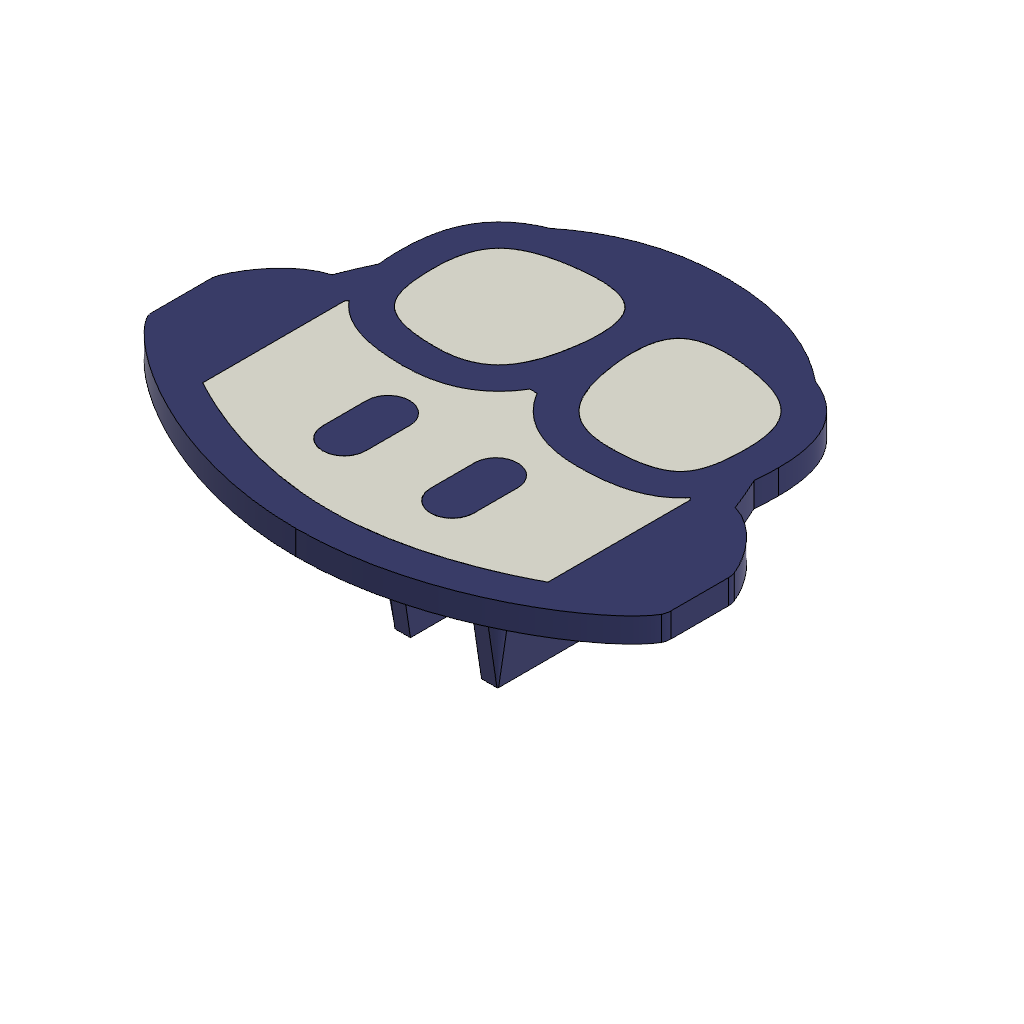
insert-copilot (Autodesk Fusion 360 design; units mm, degrees)
Autodesk Fusion 360 part; units mm, degrees
sketch "dot profile" plane through (0, 0, 0) normal (0, 0, 1) x (1, 0, 0)
  line L0 (0, 1.75) -> (0, 22.5) construction
  line L1 (1.75, 0) -> (22.5, 0) construction
  line L2 (1.25, 1.75) -> (-1.25, 1.75) construction
  line L3 (-1.75, 1.25) -> (-1.75, -1.25) construction
  line L4 (-1.25, -1.75) -> (1.25, -1.75) construction
  line L5 (1.75, -1.25) -> (1.75, 1.25) construction
  arc A0 (1.75, 1.25) -> (1.25, 1.75) centre (1.25, 1.25) ccw construction
  arc A1 (-1.25, 1.75) -> (-1.75, 1.25) centre (-1.25, 1.25) ccw construction
  arc A2 (-1.75, -1.25) -> (-1.25, -1.75) centre (-1.25, -1.25) ccw construction
  arc A3 (1.25, -1.75) -> (1.75, -1.25) centre (1.25, -1.25) ccw construction
  line L6 (0, 1.75) -> (0, 0) construction
  line L7 (0, 0) -> (-1.75, 0) construction
  arc A4 (-1.25, 1.57) -> (-1.57, 1.25) centre (-1.25, 1.25) ccw
  line L8 (-1.57, 1.25) -> (-1.57, -1.25)
  arc A5 (-1.57, -1.25) -> (-1.25, -1.57) centre (-1.25, -1.25) ccw
  line L9 (-1.25, -1.57) -> (1.25, -1.57)
  arc A6 (1.25, -1.57) -> (1.57, -1.25) centre (1.25, -1.25) ccw
  line L10 (1.57, -1.25) -> (1.57, 1.25)
  arc A7 (1.57, 1.25) -> (1.25, 1.57) centre (1.25, 1.25) ccw
  line L11 (1.25, 1.57) -> (-1.25, 1.57)
  dimension "d36" = 0.5
  dimension "d37" = 3.5
  dimension "d38" = -0.18
  constraint horizontal L2
  constraint vertical L3
  constraint horizontal L4
  constraint vertical L5
  constraint tangent L2 A0
  constraint tangent L5 A0
  constraint tangent L2 A1
  constraint tangent L3 A1
  constraint equal A0 A1
  constraint tangent L3 A2
  constraint tangent L4 A2
  constraint equal A0 A2
  constraint tangent L4 A3
  constraint tangent L5 A3
  constraint equal A0 A3
  constraint equal L2 L3
  constraint midpoint L2 L0.start
  constraint perpendicular L4 L6
  constraint midpoint L3 L7.end
  constraint horizontal L7
  constraint coincident L6.end L7.start
  measures "d36" radius of A0
  measures "d37" distance of L2 L4
sketch "logo profile" plane through (0, 0, 0) normal (0, 0, 1) x (1, 0, 0)
  spline S0 degree 3 poles (6.3059, -2.2969) (5.8508, -3.0875) (3.2087, -4.9525) (0.0035, -4.9525) knots 0 0 0 0 1 1 1 1
  spline S1 degree 3 poles (0.0035, -4.9525) (-3.2017, -4.9525) (-5.8438, -3.0875) (-6.2989, -2.2969) knots 0 0 0 0 1 1 1 1
  arc A0 (-6.2989, -2.2969) -> (-6.3415, -2.1461) centre (-5.9955, -2.1298) cw
  line L0 (-6.3415, -2.1461) -> (-6.3415, -0.6604)
  spline S2 degree 3 poles (-6.3415, -0.6604) (-6.3383, -0.6154) (-6.329, -0.571) (-6.3124, -0.5287) knots 0 0 0 0 1 1 1 1
  spline S3 degree 3 poles (-6.3124, -0.5287) (-6.1155, -0.0347) (-5.6001, 0.6831) (-4.935, 0.8757) knots 0 0 0 0 1 1 1 1
  spline S4 degree 3 poles (-4.935, 0.8757) (-4.8468, 1.102) (-4.7164, 1.433) (-4.5944, 1.6772) knots 0 0 0 0 1 1 1 1
  arc A1 (-4.5944, 1.6772) -> (-4.6219, 2.2516) centre (0.6992, 2.2186) cw
  spline S5 degree 3 poles (-4.6219, 2.2516) (-4.6219, 2.9551) (-4.473, 3.5724) (-4.0235, 4.032) knots 0 0 0 0 1 1 1 1
  spline S6 degree 3 poles (-4.0235, 4.032) (-3.8136, 4.2465) (-3.5533, 4.4111) (-3.2443, 4.5349) knots 0 0 0 0 1 1 1 1
  spline S7 degree 3 poles (-3.2443, 4.5349) (-2.5045, 5.1358) (-1.4512, 5.6414) (-0.0079, 5.6414) knots 0 0 0 0 1 1 1 1
  spline S8 degree 3 poles (-0.0079, 5.6414) (1.4354, 5.6414) (2.5117, 5.1358) (3.2515, 4.5349) knots 0 0 0 0 1 1 1 1
  spline S9 degree 3 poles (3.2515, 4.5349) (3.5603, 4.4111) (3.8206, 4.2465) (4.0305, 4.032) knots 0 0 0 0 1 1 1 1
  spline S10 degree 3 poles (4.0305, 4.032) (4.48, 3.5724) (4.6292, 2.9551) (4.6292, 2.2516) knots 0 0 0 0 1 1 1 1
  spline S11 degree 3 poles (4.6292, 2.2516) (4.6292, 2.0568) (4.6221, 1.864) (4.6014, 1.6772) knots 0 0 0 0 1 1 1 1
  spline S12 degree 3 poles (4.6014, 1.6772) (4.7234, 1.433) (4.8538, 1.102) (4.9422, 0.8757) knots 0 0 0 0 1 1 1 1
  spline S13 degree 3 poles (4.9422, 0.8757) (5.6071, 0.6831) (6.1225, -0.0347) (6.3194, -0.5287) knots 0 0 0 0 1 1 1 1
  spline S14 degree 3 poles (6.3194, -0.5287) (6.3408, -0.5829) (6.3498, -0.6408) (6.3498, -0.6993) knots 0 0 0 0 1 1 1 1
  line L1 (6.3498, -0.6993) -> (6.3498, -2.1064)
  spline S15 degree 3 poles (6.3498, -2.1064) (6.3498, -2.1731) (6.3392, -2.2392) (6.3059, -2.2969) knots 0 0 0 0 1 1 1 1
  line L2 (0.0945, 0.8707) -> (-0.0875, 0.8707)
  arc A2 (-0.0875, 0.8707) -> (-0.2751, 0.6019) centre (-2.0251, 2.0229) cw
  spline S16 degree 3 poles (-0.2751, 0.6019) (-0.6818, 0.1013) (-1.2893, -0.1866) (-2.1293, -0.1866) knots 0 0 0 0 1 1 1 1
  spline S17 degree 3 poles (-2.1293, -0.1866) (-3.0413, -0.1866) (-3.7094, 0.0031) (-4.1288, 0.4786) knots 0 0 0 0 1 1 1 1
  arc A3 (-4.1288, 0.4786) -> (-4.174, 0.5342) centre (-3.2474, 1.2425) cw
  line L3 (-4.174, 0.5342) -> (-4.2256, 0.4786)
  line L4 (-4.2256, 0.4786) -> (-4.2256, -3.002)
  spline S18 degree 3 poles (-4.2256, -3.002) (-3.467, -3.4142) (-1.8391, -4.1537) (0.0035, -4.1537) knots 0 0 0 0 1 1 1 1
  spline S19 degree 3 poles (0.0035, -4.1537) (1.8461, -4.1537) (3.474, -3.4142) (4.2326, -3.002) knots 0 0 0 0 1 1 1 1
  line L5 (4.2326, -3.002) -> (4.2326, 0.4786)
  line L6 (4.2326, 0.4786) -> (4.181, 0.5342)
  spline S20 degree 2 poles (4.181, 0.5342) (4.1635, 0.5101) (4.1358, 0.4786) knots 0 0 0 1 1 1
  spline S21 degree 3 poles (4.1358, 0.4786) (3.7167, 0.0031) (3.0483, -0.1866) (2.1363, -0.1866) knots 0 0 0 0 1 1 1 1
  spline S22 degree 3 poles (2.1363, -0.1866) (1.2963, -0.1866) (0.689, 0.1013) (0.2821, 0.6019) knots 0 0 0 0 1 1 1 1
  arc A4 (0.2821, 0.6019) -> (0.0945, 0.8707) centre (2.0575, 2.0407) cw
  line L7 (0.0945, 0.8707) -> (0.0858, 0.8707)
  line L8 (0.0858, 0.8707) -> (0.0945, 0.8707)
  arc A5 (-0.3928, 2.8945) -> (-0.4264, 2.4222) centre (-4.1789, 2.9266) cw
  line L9 (-0.3928, 2.8945) -> (-0.3928, 2.9056)
  spline S23 degree 3 poles (-0.3928, 2.9056) (-0.3936, 3.3123) (-0.4825, 3.5771) (-0.6246, 3.7396) knots 0 0 0 0 1 1 1 1
  spline S24 degree 3 poles (-0.6246, 3.7396) (-0.8048, 3.946) (-1.1776, 4.1042) (-1.9634, 4.0193) knots 0 0 0 0 1 1 1 1
  spline S25 degree 3 poles (-1.9634, 4.0193) (-2.7593, 3.933) (-3.2043, 3.7354) (-3.4565, 3.4774) knots 0 0 0 0 1 1 1 1
  spline S26 degree 3 poles (-3.4565, 3.4774) (-3.7007, 3.2276) (-3.829, 2.854) (-3.829, 2.2516) knots 0 0 0 0 1 1 1 1
  spline S27 degree 3 poles (-3.829, 2.2516) (-3.829, 1.6113) (-3.7369, 1.2332) (-3.534, 1.003) knots 0 0 0 0 1 1 1 1
  spline S28 degree 3 poles (-3.534, 1.003) (-3.3411, 0.7842) (-2.9612, 0.6064) (-2.1293, 0.6064) knots 0 0 0 0 1 1 1 1
  spline S29 degree 3 poles (-2.1293, 0.6064) (-1.4898, 0.6064) (-1.1242, 0.8144) (-0.8903, 1.102) knots 0 0 0 0 1 1 1 1
  spline S30 degree 3 poles (-0.8903, 1.102) (-0.6394, 1.411) (-0.4982, 1.8634) (-0.4264, 2.4222) knots 0 0 0 0 1 1 1 1
  spline S31 degree 3 poles (0.4334, 2.4222) (0.5051, 1.8634) (0.6464, 1.411) (0.8975, 1.102) knots 0 0 0 0 1 1 1 1
  spline S32 degree 3 poles (0.8975, 1.102) (1.1312, 0.8144) (1.4968, 0.6064) (2.1363, 0.6064) knots 0 0 0 0 1 1 1 1
  spline S33 degree 3 poles (2.1363, 0.6064) (2.9684, 0.6064) (3.3481, 0.7842) (3.541, 1.003) knots 0 0 0 0 1 1 1 1
  spline S34 degree 3 poles (3.541, 1.003) (3.7439, 1.2332) (3.8363, 1.6113) (3.8363, 2.2516) knots 0 0 0 0 1 1 1 1
  spline S35 degree 3 poles (3.8363, 2.2516) (3.8363, 2.854) (3.7079, 3.2276) (3.4637, 3.4774) knots 0 0 0 0 1 1 1 1
  spline S36 degree 3 poles (3.4637, 3.4774) (3.2113, 3.7354) (2.7665, 3.933) (1.9704, 4.0193) knots 0 0 0 0 1 1 1 1
  spline S37 degree 3 poles (1.9704, 4.0193) (1.1849, 4.1042) (0.8121, 3.946) (0.6316, 3.7396) knots 0 0 0 0 1 1 1 1
  spline S38 degree 3 poles (0.6316, 3.7396) (0.4895, 3.5771) (0.4006, 3.3123) (0.3998, 2.9056) knots 0 0 0 0 1 1 1 1
  line L10 (0.3998, 2.9056) -> (0.3998, 2.8945)
  spline S39 degree 3 poles (0.3998, 2.8945) (0.4004, 2.7543) (0.411, 2.5974) (0.4334, 2.4222) knots 0 0 0 0 1 1 1 1
  spline S40 degree 3 poles (1.3309, -0.8451) (1.623, -0.8451) (1.8598, -1.0819) (1.8598, -1.374) knots 0 0 0 0 1 1 1 1
  line L11 (1.8598, -1.374) -> (1.8598, -2.4318)
  arc A6 (1.8598, -2.4318) -> (0.802, -2.4318) centre (1.3309, -2.4485) cw
  line L12 (0.802, -2.4318) -> (0.802, -1.374)
  spline S41 degree 3 poles (0.802, -1.374) (0.802, -1.0819) (1.0388, -0.8451) (1.3309, -0.8451) knots 0 0 0 0 1 1 1 1
  spline S42 degree 3 poles (-1.3139, -0.8451) (-1.0218, -0.8451) (-0.785, -1.0819) (-0.785, -1.374) knots 0 0 0 0 1 1 1 1
  line L13 (-0.785, -1.374) -> (-0.785, -2.4318)
  arc A7 (-0.785, -2.4318) -> (-1.8428, -2.4318) centre (-1.3139, -2.4485) cw
  line L14 (-1.8428, -2.4318) -> (-1.8428, -1.374)
  spline S43 degree 3 poles (-1.8428, -1.374) (-1.8428, -1.0819) (-1.606, -0.8451) (-1.3139, -0.8451) knots 0 0 0 0 1 1 1 1
extrude "face1" add sketch "logo profile" along normal blind 0.6 contours S0 S1 A0 L0 S2 S3 S4 A1 S5 S6 S7 S8 S9 S10 S11 S12 S13 S14 L1 S15 | L2 A2 S16 S17 A3 L3 L4 S18 S19 L5 L6 S20 S21 S22 A4 L7 L8 | A5 L9 S23 S24 S25 S26 S27 S28 S29 S30 | S31 S32 S33 S34 S35 S36 S37 S38 L10 S39 | S40 L11 A6 L12 S41 | S42 L13 A7 L14 S43 makes body 1
sketch "face" plane through (0, 0, 0.6) normal (0, 0, 1) x (-1, 0, 0)
  line L0 (-6.3498, 2.1064) -> (-6.3498, 0.6993)
  spline S0 degree 3 poles (-6.3498, 0.6993) (-6.3498, 0.6408) (-6.3408, 0.5829) (-6.3194, 0.5287) knots -1 -1 -1 -1 0 0 0 0
  spline S1 degree 3 poles (-6.3194, 0.5287) (-6.1225, 0.0347) (-5.6071, -0.6831) (-4.9422, -0.8757) knots -1 -1 -1 -1 0 0 0 0
  spline S2 degree 3 poles (-4.9422, -0.8757) (-4.8538, -1.102) (-4.7234, -1.433) (-4.6014, -1.6772) knots -1 -1 -1 -1 0 0 0 0
  spline S3 degree 3 poles (-4.6014, -1.6772) (-4.6221, -1.864) (-4.6292, -2.0568) (-4.6292, -2.2516) knots -1 -1 -1 -1 0 0 0 0
  spline S4 degree 3 poles (-4.6292, -2.2516) (-4.6292, -2.9551) (-4.48, -3.5724) (-4.0305, -4.032) knots -1 -1 -1 -1 0 0 0 0
  spline S5 degree 3 poles (-4.0305, -4.032) (-3.8206, -4.2465) (-3.5603, -4.4111) (-3.2515, -4.5349) knots -1 -1 -1 -1 0 0 0 0
  spline S6 degree 3 poles (-3.2515, -4.5349) (-2.5117, -5.1358) (-1.4354, -5.6414) (0.0079, -5.6414) knots -1 -1 -1 -1 0 0 0 0
  spline S7 degree 3 poles (0.0079, -5.6414) (1.4512, -5.6414) (2.5045, -5.1358) (3.2443, -4.5349) knots -1 -1 -1 -1 0 0 0 0
  spline S8 degree 3 poles (3.2443, -4.5349) (3.5533, -4.4111) (3.8136, -4.2465) (4.0235, -4.032) knots -1 -1 -1 -1 0 0 0 0
  spline S9 degree 3 poles (4.0235, -4.032) (4.473, -3.5724) (4.6219, -2.9551) (4.6219, -2.2516) knots -1 -1 -1 -1 0 0 0 0
  arc A0 (4.6219, -2.2516) -> (4.5944, -1.6772) centre (-0.6992, -2.2186) ccw
  spline S10 degree 3 poles (4.5944, -1.6772) (4.7164, -1.433) (4.8468, -1.102) (4.935, -0.8757) knots -1 -1 -1 -1 0 0 0 0
  spline S11 degree 3 poles (4.935, -0.8757) (5.6001, -0.6831) (6.1155, 0.0347) (6.3124, 0.5287) knots -1 -1 -1 -1 0 0 0 0
  spline S12 degree 3 poles (6.3124, 0.5287) (6.329, 0.571) (6.3383, 0.6154) (6.3415, 0.6604) knots -1 -1 -1 -1 0 0 0 0
  line L1 (6.3415, 0.6604) -> (6.3415, 2.1461)
  arc A1 (6.3415, 2.1461) -> (6.2989, 2.2969) centre (5.9955, 2.1298) ccw
  spline S13 degree 3 poles (6.2989, 2.2969) (5.8438, 3.0875) (3.2017, 4.9525) (-0.0035, 4.9525) knots -1 -1 -1 -1 0 0 0 0
  spline S14 degree 3 poles (-0.0035, 4.9525) (-3.2087, 4.9525) (-5.8508, 3.0875) (-6.3059, 2.2969) knots -1 -1 -1 -1 0 0 0 0
  spline S15 degree 3 poles (-6.3059, 2.2969) (-6.3392, 2.2392) (-6.3498, 2.1731) (-6.3498, 2.1064) knots -1 -1 -1 -1 0 0 0 0
  spline S16 degree 3 poles (3.4565, -3.4774) (3.7007, -3.2276) (3.829, -2.854) (3.829, -2.2516) knots 0 0 0 0 1 1 1 1
  spline S17 degree 3 poles (1.9634, -4.0193) (2.7593, -3.933) (3.2043, -3.7354) (3.4565, -3.4774) knots 0 0 0 0 1 1 1 1
  spline S18 degree 3 poles (0.6246, -3.7396) (0.8048, -3.946) (1.1776, -4.1042) (1.9634, -4.0193) knots 0 0 0 0 1 1 1 1
  spline S19 degree 3 poles (0.3928, -2.9056) (0.3936, -3.3123) (0.4825, -3.5771) (0.6246, -3.7396) knots 0 0 0 0 1 1 1 1
  arc A2 (0.4264, -2.4222) -> (0.3928, -2.8945) centre (4.1789, -2.9266) ccw
  spline S20 degree 3 poles (0.8903, -1.102) (0.6394, -1.411) (0.4982, -1.8634) (0.4264, -2.4222) knots 0 0 0 0 1 1 1 1
  spline S21 degree 3 poles (2.1293, -0.6064) (1.4898, -0.6064) (1.1242, -0.8144) (0.8903, -1.102) knots 0 0 0 0 1 1 1 1
  spline S22 degree 3 poles (3.534, -1.003) (3.3411, -0.7842) (2.9612, -0.6064) (2.1293, -0.6064) knots 0 0 0 0 1 1 1 1
  spline S23 degree 3 poles (3.829, -2.2516) (3.829, -1.6113) (3.7369, -1.2332) (3.534, -1.003) knots 0 0 0 0 1 1 1 1
  line L2 (0.3928, -2.8945) -> (0.3928, -2.9056)
  spline S24 degree 3 poles (-1.9704, -4.0193) (-1.1849, -4.1042) (-0.8121, -3.946) (-0.6316, -3.7396) knots 0 0 0 0 1 1 1 1
  spline S25 degree 3 poles (-0.6316, -3.7396) (-0.4895, -3.5771) (-0.4006, -3.3123) (-0.3998, -2.9056) knots 0 0 0 0 1 1 1 1
  spline S26 degree 3 poles (-0.3998, -2.8945) (-0.4004, -2.7543) (-0.411, -2.5974) (-0.4334, -2.4222) knots 0 0 0 0 1 1 1 1
  line L3 (-0.3998, -2.9056) -> (-0.3998, -2.8945)
  spline S27 degree 3 poles (-0.4334, -2.4222) (-0.5051, -1.8634) (-0.6464, -1.411) (-0.8975, -1.102) knots 0 0 0 0 1 1 1 1
  spline S28 degree 3 poles (-0.8975, -1.102) (-1.1312, -0.8144) (-1.4968, -0.6064) (-2.1363, -0.6064) knots 0 0 0 0 1 1 1 1
  spline S29 degree 3 poles (-2.1363, -0.6064) (-2.9684, -0.6064) (-3.3481, -0.7842) (-3.541, -1.003) knots 0 0 0 0 1 1 1 1
  spline S30 degree 3 poles (-3.541, -1.003) (-3.7439, -1.2332) (-3.8363, -1.6113) (-3.8363, -2.2516) knots 0 0 0 0 1 1 1 1
  spline S31 degree 3 poles (-3.8363, -2.2516) (-3.8363, -2.854) (-3.7079, -3.2276) (-3.4637, -3.4774) knots 0 0 0 0 1 1 1 1
  spline S32 degree 3 poles (-3.4637, -3.4774) (-3.2113, -3.7354) (-2.7665, -3.933) (-1.9704, -4.0193) knots 0 0 0 0 1 1 1 1
  line L4 (-0.0945, -0.8707) -> (0.0875, -0.8707)
  arc A3 (0.2751, -0.6019) -> (0.0875, -0.8707) centre (2.0251, -2.0229) ccw
  spline S33 degree 3 poles (0.2751, -0.6019) (0.6818, -0.1013) (1.2893, 0.1866) (2.1293, 0.1866) knots 0 0 0 0 1 1 1 1
  spline S34 degree 3 poles (2.1293, 0.1866) (3.0413, 0.1866) (3.7094, -0.0031) (4.1288, -0.4786) knots 0 0 0 0 1 1 1 1
  arc A4 (4.174, -0.5342) -> (4.1288, -0.4786) centre (3.2474, -1.2425) ccw
  line L5 (4.174, -0.5342) -> (4.2256, -0.4786)
  line L6 (4.2256, -0.4786) -> (4.2256, 3.002)
  spline S35 degree 3 poles (4.2256, 3.002) (3.467, 3.4142) (1.8391, 4.1537) (-0.0035, 4.1537) knots 0 0 0 0 1 1 1 1
  spline S36 degree 3 poles (-0.0035, 4.1537) (-1.8461, 4.1537) (-3.474, 3.4142) (-4.2326, 3.002) knots 0 0 0 0 1 1 1 1
  line L7 (-4.2326, 3.002) -> (-4.2326, -0.4786)
  line L8 (-4.2326, -0.4786) -> (-4.181, -0.5342)
  spline S37 degree 2 poles (-4.181, -0.5342) (-4.1635, -0.5101) (-4.1358, -0.4786) knots 0 0 0 1 1 1
  spline S38 degree 3 poles (-4.1358, -0.4786) (-3.7167, -0.0031) (-3.0483, 0.1866) (-2.1363, 0.1866) knots 0 0 0 0 1 1 1 1
  spline S39 degree 3 poles (-2.1363, 0.1866) (-1.2963, 0.1866) (-0.689, -0.1013) (-0.2821, -0.6019) knots 0 0 0 0 1 1 1 1
  arc A5 (-0.0945, -0.8707) -> (-0.2821, -0.6019) centre (-2.0575, -2.0407) ccw
  spline S40 degree 3 poles (1.8428, 1.374) (1.8428, 1.0819) (1.606, 0.8451) (1.3139, 0.8451) knots 0 0 0 0 1 1 1 1
  spline S41 degree 3 poles (1.3139, 0.8451) (1.0218, 0.8451) (0.785, 1.0819) (0.785, 1.374) knots 0 0 0 0 1 1 1 1
  line L9 (0.785, 1.374) -> (0.785, 2.4318)
  line L10 (1.8428, 2.4318) -> (1.8428, 1.374)
  arc A6 (1.8428, 2.4318) -> (0.785, 2.4318) centre (1.3139, 2.4485) ccw
  spline S42 degree 3 poles (-0.802, 1.374) (-0.802, 1.0819) (-1.0388, 0.8451) (-1.3309, 0.8451) knots 0 0 0 0 1 1 1 1
  spline S43 degree 3 poles (-1.3309, 0.8451) (-1.623, 0.8451) (-1.8598, 1.0819) (-1.8598, 1.374) knots 0 0 0 0 1 1 1 1
  line L11 (-1.8598, 1.374) -> (-1.8598, 2.4318)
  arc A7 (-0.802, 2.4318) -> (-1.8598, 2.4318) centre (-1.3309, 2.4485) ccw
  line L12 (-0.802, 2.4318) -> (-0.802, 1.374)
extrude "Extrude5" add sketch "face" against normal blind 0.4 separate body contours S16 S17 S18 S19 A2 S20 S21 S22 S23 L2 | S24 S25 S26 L3 S27 S28 S29 S30 S31 S32 | L4 A3 S33 S34 A4 L5 L6 S35 S36 L7 L8 S37 S38 S39 A5 makes body 2 at (-2.3071, 2.7155, 0.6) makes body 3 at (2.2901, 2.6954, 0.6) makes body 4 at (-3.105, -1.4763, 0.6)
combine "Combine1" operation cut target body 1 tool bodies 3 2 4 keep tools
extrude "pin" add sketch "dot profile" against normal blind 4 separate body makes body 5
chamfer "pin chamfer" distance 0.3 distance2 2 8 edges at (-1.57, 0, -4) (-1.4763, 1.4763, -4) (0, 1.57, -4) (1.4763, 1.4763, -4) (1.57, 0, -4) (1.4763, -1.4763, -4) (0, -1.57, -4) (-1.4763, -1.4763, -4) measured on face at (0.5233, -0.4167, -4) measured on face at (0.5233, -0.4167, -4) measured on face at (0.5233, -0.4167, -4) measured on face at (0.5233, -0.4167, -4) measured on face at (0.5233, -0.4167, -4) measured on face at (0.5233, -0.4167, -4) measured on face at (0.5233, -0.4167, -4) measured on face at (0.5233, -0.4167, -4) tangent chain off on bodies 5
sketch "Sketch10" plane through (0, 0, 0) normal (0, 0, -1) x (1, 0, 0)
  line L0 (6.3498, 0.6993) -> (6.3498, 2.1064)
  spline S0 degree 3 poles (6.3498, 2.1064) (6.3498, 2.1731) (6.3392, 2.2392) (6.3059, 2.2969) knots 0 0 0 0 1 1 1 1
  spline S1 degree 3 poles (6.3059, 2.2969) (5.8508, 3.0875) (3.2087, 4.9525) (0.0035, 4.9525) knots 0 0 0 0 1 1 1 1
  spline S2 degree 3 poles (0.0035, 4.9525) (-3.2017, 4.9525) (-5.8438, 3.0875) (-6.2989, 2.2969) knots 0 0 0 0 1 1 1 1
  arc A0 (-6.2989, 2.2969) -> (-6.3415, 2.1461) centre (-5.9955, 2.1298) ccw
  line L1 (-6.3415, 2.1461) -> (-6.3415, 0.6604)
  spline S3 degree 3 poles (-6.3415, 0.6604) (-6.3383, 0.6154) (-6.329, 0.571) (-6.3124, 0.5287) knots 0 0 0 0 1 1 1 1
  spline S4 degree 3 poles (-6.3124, 0.5287) (-6.1155, 0.0347) (-5.6001, -0.6831) (-4.935, -0.8757) knots 0 0 0 0 1 1 1 1
  spline S5 degree 3 poles (-4.935, -0.8757) (-4.8468, -1.102) (-4.7164, -1.433) (-4.5944, -1.6772) knots 0 0 0 0 1 1 1 1
  arc A1 (-4.5944, -1.6772) -> (-4.6219, -2.2516) centre (0.6992, -2.2186) ccw
  spline S6 degree 3 poles (-4.6219, -2.2516) (-4.6219, -2.9551) (-4.473, -3.5724) (-4.0235, -4.032) knots 0 0 0 0 1 1 1 1
  spline S7 degree 3 poles (-4.0235, -4.032) (-3.8136, -4.2465) (-3.5533, -4.4111) (-3.2443, -4.5349) knots 0 0 0 0 1 1 1 1
  spline S8 degree 3 poles (-3.2443, -4.5349) (-2.5045, -5.1358) (-1.4512, -5.6414) (-0.0079, -5.6414) knots 0 0 0 0 1 1 1 1
  spline S9 degree 3 poles (-0.0079, -5.6414) (1.4354, -5.6414) (2.5117, -5.1358) (3.2515, -4.5349) knots 0 0 0 0 1 1 1 1
  spline S10 degree 3 poles (3.2515, -4.5349) (3.5603, -4.4111) (3.8206, -4.2465) (4.0305, -4.032) knots 0 0 0 0 1 1 1 1
  spline S11 degree 3 poles (4.0305, -4.032) (4.48, -3.5724) (4.6292, -2.9551) (4.6292, -2.2516) knots 0 0 0 0 1 1 1 1
  spline S12 degree 3 poles (4.6292, -2.2516) (4.6292, -2.0568) (4.6221, -1.864) (4.6014, -1.6772) knots 0 0 0 0 1 1 1 1
  spline S13 degree 3 poles (4.6014, -1.6772) (4.7234, -1.433) (4.8538, -1.102) (4.9422, -0.8757) knots 0 0 0 0 1 1 1 1
  spline S14 degree 3 poles (4.9422, -0.8757) (5.6071, -0.6831) (6.1225, 0.0347) (6.3194, 0.5287) knots 0 0 0 0 1 1 1 1
  spline S15 degree 3 poles (6.3194, 0.5287) (6.3408, 0.5829) (6.3498, 0.6408) (6.3498, 0.6993) knots 0 0 0 0 1 1 1 1
  line L2 (-1.25, 1.57) -> (1.25, 1.57)
  line L3 (1.25, -1.57) -> (-1.25, -1.57)
  line L4 (-1.27, -1.25) -> (-1.27, 1.25) construction
  line L5 (1.27, 1.25) -> (1.27, -1.25) construction
  line L6 (0.87, -1.57) -> (0.87, 1.57)
  line L7 (-0.87, -1.57) -> (-0.87, 1.57)
  dimension "d39" = 0.4
  dimension "d40" = 0.4
  constraint coincident L3 L6.start
  constraint coincident L2 L6.end
  constraint perpendicular L2 L6
  constraint coincident L3 L7.start
  constraint coincident L2 L7.end
  constraint perpendicular L2 L7
  measures "d39" distance of L4 L7
  measures "d40" distance of L5 L6
extrude "Extrude6" cut sketch "Sketch10" along normal through all from surface at 1 contours L2 L3 L6 L7 bodies 5
equation "d6 = -cell_depth"
equation "printing_layer_height = 0.2 mm"
equation "cell_depth = 20 * printing_layer_height"
named bodies: "body", "goggle-1", "goggle-2", "face"
